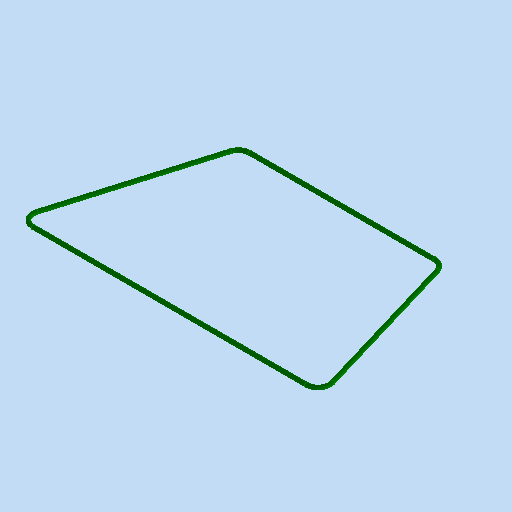
# Autodesk Inventor part: MM0948AN220_G02_101
Saved by Autodesk Inventor 2023.3 (Build 273359000, 359)
## iProperties
Created: 2023-12-11
Part Number: MM0948AN220_G02_101
Material: Generisch
Description: =<RBPARTNOTITLE2>
Document SubType Name: Modeling
Designer: SFO3AN
Mass: 4.82182 g
Surface Area: 14.6116 cm^2
Volume: 0.547934 cm^3
Density: 8.8 g/cm^3
Appearance: grün AnP
Vendor: Rubix
RBPARTMADEOF: OR 80.00x1.50 FKM 80
RBDRAWINGMISSINGSPEC: --
AnP_Kategorie: 2
RBPARTNOTITLE2: O-Ring ISO 3601/1-B
RBSURFACE: --
RBPARTNOTITLE1: o-ring ISO 3601/1-B
RBSURFACE2: --
AnP_Material: =<Material>
RBMATERIAL: --
RBMATNO: =<Part Number>
RBPARTNO: SIEHE MNR
Author: SFO3AN
Keywords: =<RBPARTMADEOF>
Comments: =<RBSURFACE2>
Revision Number: 01
Autodesk Inventor part; units mm, degrees
ref_plane "YZ Plane" through (0, 0, 0) normal (1, 0, 0) x (0, 1, 0)
ref_plane "XZ Plane" through (0, 0, 0) normal (0, 1, 0) x (-1, 0, 0)
ref_plane "XY Plane" through (0, 0, 0) normal (0, 0, 1) x (1, 0, 0)
sketch "Skizze2" plane through (0, 0, 0) normal (0, 0, 1) x (1, 0, 0)
  line L0 (-78.0563, 0) -> (78.0563, 0) construction
  line L1 (0, -73.5) -> (0, 73.5) construction
  circle A0 centre (0, 0) radius 52.5 construction
  arc A1 (-34.0037, 43.5) -> (-37.3593, 40.995) centre (-34.0037, 40) ccw
  arc A2 (37.3593, 40.995) -> (34.0037, 43.5) centre (34.0037, 40) ccw
  arc A3 (50.3115, -18.5) -> (53.6671, -14.005) centre (50.3115, -15) ccw
  arc A4 (-53.6671, -14.005) -> (-50.3115, -18.5) centre (-50.3115, -15) ccw
  line L2 (-53.6671, -14.005) -> (-37.3593, 40.995)
  line L3 (-34.0037, 43.5) -> (34.0037, 43.5)
  line L4 (37.3593, 40.995) -> (53.6671, -14.005)
  line L5 (-50.3115, -18.5) -> (50.3115, -18.5)
  arc A5 (38.0783, 41.2082) -> (34.0037, 44.25) centre (34.0037, 40) ccw
  line L6 (38.0783, 41.2082) -> (54.3862, -13.7918)
  arc A6 (50.3115, -19.25) -> (54.3862, -13.7918) centre (50.3115, -15) ccw
  line L7 (50.3115, -19.25) -> (-50.3115, -19.25)
  arc A7 (-54.3862, -13.7918) -> (-50.3115, -19.25) centre (-50.3115, -15) ccw
  line L8 (-54.3862, -13.7918) -> (-38.0783, 41.2082)
  arc A8 (-34.0037, 44.25) -> (-38.0783, 41.2082) centre (-34.0037, 40) ccw
  line L9 (-34.0037, 44.25) -> (34.0037, 44.25)
  dimension "d0" = 105
  dimension "d1" = 40
  dimension "d2" = 15
  dimension "d3" = 7
  dimension "d7" = 0.75
  constraints: 20 point on circle, 16 end point, 9 centre point, 7 tangent, 3 equal radius, 1 coincident, 1 horizontal, 9 other
  measures "d0" diameter of A0
  measures "d1" distance from line of A0.start L0
  measures "d2" distance from line of A4.centre L0
  measures "d3" diameter of A2
  measures "d7" distance between parallel lines of L2 L8
sketch "Skizze4" plane through (0, 0, 0) normal (1, 0, 0) x (0, 1, 0)
  circle A0 centre (-18.5, 0) radius 0.75
  line L0 (0, -1.05) -> (0, 1.05) projected
  line L1 (-24, 0) -> (4, 0) projected
  circle A1 centre (-19.25, 0) radius 0.75
  point P0 (0, 0)
  dimension "d4" = 1.5
  dimension "d8" = 0.75
  constraints: 2 centre point, 1 coincident, 1 equal radius, 1 point on line
  measures "d4" diameter of A0
  measures "d8" distance of point (-18.5, 0) A1.centre
sweep "Sweeping1" add profiles "Skizze4" path "Skizze2" picked at (-18.7555, 0.052) picked at (-19.7433, 0.0577) picked at (-19.7433, -0.0577) picked at (-18.7555, -0.052) path curves L3 A1 L2 A4 L5 A3 L4 A2 contours A1 L1 A0 | A0 L1 A1 | A1 L1 A0 | A0 L1 A1
